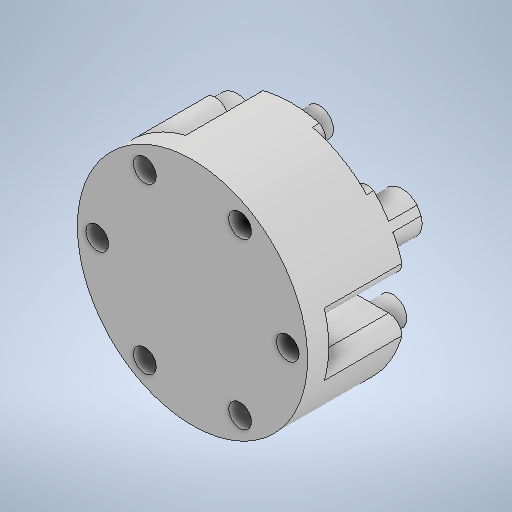
# Autodesk Inventor part: J1_J2_FLANGE
Saved by Autodesk Inventor 2025.4 (Build 294407000, 407)
## iProperties
Created: 2026-07-24
Part Number: J1_J2_FLANGE
Material: 常规
Document SubType Name: Modeling
Designer: Admin
Density: 1 g/cm^3
Appearance: 默认
Author: Admin
Autodesk Inventor part; units mm, degrees
ref_plane "YZ Plane" through (0, 0, 0) normal (1, 0, 0) x (0, 1, 0)
ref_plane "XZ Plane" through (0, 0, 0) normal (0, 1, 0) x (-1, 0, 0)
ref_plane "XY Plane" through (0, 0, 0) normal (0, 0, 1) x (1, 0, 0)
sketch "草图7" plane through (0, 0, 0) normal (0, 0, 1) x (1, 0, 0)
  line L0 (13.784, 2.5) -> (13.5, 2.5)
  line L1 (9.0571, 10.6873) -> (8.9151, 10.4413)
  arc A0 (12.2773, 11.0235) -> (9.0571, 10.6873) centre (10.7891, 9.6873) ccw
  arc A1 (15.6853, 5.1207) -> (12.2773, 11.0235) centre (0, 0) ccw
  arc A2 (13.784, 2.5) -> (15.6853, 5.1207) centre (13.784, 4.5) ccw
  circle A3 centre (0, 0) radius 17.5
  arc A4 (8.7635, -2.0496) -> (3.5969, 8.25) centre (0, 0) ccw
  line L2 (8.9151, 10.4413) -> (6.488, 6.2375)
  line L3 (6.488, 6.2375) -> (8.6458, 2.5)
  line L4 (8.6458, 2.5) -> (13.5, 2.5)
  line L5 (4.727, 13.1873) -> (4.5849, 12.9413)
  arc A5 (3.408, 16.1442) -> (-3.408, 16.1442) centre (0, 0) ccw
  arc A6 (4.727, 13.1873) -> (3.408, 16.1442) centre (2.9949, 14.1873) ccw
  line L6 (2.1578, 8.7375) -> (4.5849, 12.9413)
  line L7 (-4.727, 13.1873) -> (-4.5849, 12.9413)
  arc A7 (-3.408, 16.1442) -> (-4.727, 13.1873) centre (-2.9949, 14.1873) ccw
  line L8 (-4.5849, 12.9413) -> (-2.1578, 8.7375)
  line L9 (-2.1578, 8.7375) -> (2.1578, 8.7375)
  line L10 (-9.0571, 10.6873) -> (-8.9151, 10.4413)
  arc A8 (-12.2773, 11.0235) -> (-15.6853, 5.1207) centre (0, 0) ccw
  arc A9 (-9.0571, 10.6873) -> (-12.2773, 11.0235) centre (-10.7891, 9.6873) ccw
  line L11 (-6.488, 6.2375) -> (-8.9151, 10.4413)
  line L12 (-13.784, 2.5) -> (-13.5, 2.5)
  arc A10 (-15.6853, 5.1207) -> (-13.784, 2.5) centre (-13.784, 4.5) ccw
  line L13 (-13.5, 2.5) -> (-8.6458, 2.5)
  line L14 (-8.6458, 2.5) -> (-6.488, 6.2375)
  line L15 (-13.784, -2.5) -> (-13.5, -2.5)
  arc A11 (-15.6853, -5.1207) -> (-12.2773, -11.0235) centre (0, 0) ccw
  arc A12 (-13.784, -2.5) -> (-15.6853, -5.1207) centre (-13.784, -4.5) ccw
  line L16 (-8.6458, -2.5) -> (-13.5, -2.5)
  line L17 (-9.0571, -10.6873) -> (-8.9151, -10.4413)
  arc A13 (-12.2773, -11.0235) -> (-9.0571, -10.6873) centre (-10.7891, -9.6873) ccw
  line L18 (-8.9151, -10.4413) -> (-6.488, -6.2375)
  line L19 (-6.488, -6.2375) -> (-8.6458, -2.5)
  line L20 (-4.727, -13.1873) -> (-4.5849, -12.9413)
  arc A14 (-3.408, -16.1442) -> (3.408, -16.1442) centre (0, 0) ccw
  arc A15 (-4.727, -13.1873) -> (-3.408, -16.1442) centre (-2.9949, -14.1873) ccw
  line L21 (-2.1578, -8.7375) -> (-4.5849, -12.9413)
  line L22 (4.727, -13.1873) -> (4.5849, -12.9413)
  arc A16 (3.408, -16.1442) -> (4.727, -13.1873) centre (2.9949, -14.1873) ccw
  line L23 (4.5849, -12.9413) -> (2.1578, -8.7375)
  line L24 (2.1578, -8.7375) -> (-2.1578, -8.7375)
  line L25 (9.0571, -10.6873) -> (8.9151, -10.4413)
  arc A17 (12.2773, -11.0235) -> (15.6853, -5.1207) centre (0, 0) ccw
  arc A18 (9.0571, -10.6873) -> (12.2773, -11.0235) centre (10.7891, -9.6873) ccw
  line L26 (6.488, -6.2375) -> (8.9151, -10.4413)
  line L27 (13.784, -2.5) -> (13.5, -2.5)
  arc A19 (15.6853, -5.1207) -> (13.784, -2.5) centre (13.784, -4.5) ccw
  line L28 (13.5, -2.5) -> (8.6458, -2.5)
  line L29 (8.6458, -2.5) -> (6.488, -6.2375)
  point P0 (0, 0)
  dimension "d25" = 9
  dimension "d26" = 35
  dimension "d27" = 2
  dimension "d28" = 2
  dimension "d29" = 16.5
  dimension "d32" = 360
  constraints: 60 end point, 39 point on circle, 20 centre point, 4 coincident, 2 collinear, 1 equal length, 113 other
  measures "d25" radius of A4
  measures "d26" diameter of A3
  measures "d27" radius of A0
  measures "d28" radius of A2
  measures "d29" radius of A1
extrude "拉伸7" add sketch "草图7" against normal blind 1 contours L0 L4 A4 L2 L1 A0 A1 A2 | L3 A4 | L5 L6 L9 L8 L7 A7 A5 A6 | L10 L11 L14 L13 L12 A10 A8 A9 | L15 L16 L19 L18 L17 A13 A11 A12 | L20 L21 L24 L23 L22 A16 A14 A15 | L25 L26 L29 L28 L27 A19 A17 A18
sketch "草图8" plane through (0, 0, 0) normal (0, 0, 1) x (1, 0, 0)
  point P0 (0, 0)
sketch "草图9" plane through (0, 0, 0) normal (0, 0, 1) x (1, 0, 0)
  line L0 (9.0571, 10.6873) -> (6.488, 6.2375) projected
  line L1 (6.488, 6.2375) -> (8.6458, 2.5) projected
  line L2 (8.6458, 2.5) -> (13.784, 2.5) projected
  arc A0 (13.784, 2.5) -> (15.6853, 5.1207) centre (13.784, 4.5) ccw projected
  arc A1 (15.6853, 5.1207) -> (12.2773, 11.0235) centre (0, 0) ccw projected
  arc A2 (12.2773, 11.0235) -> (9.0571, 10.6873) centre (10.7891, 9.6873) ccw projected
  arc A3 (-3.408, 16.1442) -> (-4.727, 13.1873) centre (-2.9949, 14.1873) ccw projected
  line L3 (-4.727, 13.1873) -> (-2.1578, 8.7375) projected
  line L4 (-2.1578, 8.7375) -> (2.1578, 8.7375) projected
  line L5 (2.1578, 8.7375) -> (4.727, 13.1873) projected
  arc A4 (4.727, 13.1873) -> (3.408, 16.1442) centre (2.9949, 14.1873) ccw projected
  arc A5 (3.408, 16.1442) -> (-3.408, 16.1442) centre (0, 0) ccw projected
  arc A6 (15.6853, -5.1207) -> (13.784, -2.5) centre (13.784, -4.5) ccw projected
  line L6 (13.784, -2.5) -> (8.6458, -2.5) projected
  line L7 (8.6458, -2.5) -> (6.488, -6.2375) projected
  line L8 (6.488, -6.2375) -> (9.0571, -10.6873) projected
  arc A7 (9.0571, -10.6873) -> (12.2773, -11.0235) centre (10.7891, -9.6873) ccw projected
  arc A8 (12.2773, -11.0235) -> (15.6853, -5.1207) centre (0, 0) ccw projected
  arc A9 (3.408, -16.1442) -> (4.727, -13.1873) centre (2.9949, -14.1873) ccw projected
  line L9 (4.727, -13.1873) -> (2.1578, -8.7375) projected
  line L10 (2.1578, -8.7375) -> (-2.1578, -8.7375) projected
  line L11 (-2.1578, -8.7375) -> (-4.727, -13.1873) projected
  arc A10 (-4.727, -13.1873) -> (-3.408, -16.1442) centre (-2.9949, -14.1873) ccw projected
  arc A11 (-3.408, -16.1442) -> (3.408, -16.1442) centre (0, 0) ccw projected
  arc A12 (-12.2773, -11.0235) -> (-9.0571, -10.6873) centre (-10.7891, -9.6873) ccw projected
  line L12 (-9.0571, -10.6873) -> (-6.488, -6.2375) projected
  line L13 (-6.488, -6.2375) -> (-8.6458, -2.5) projected
  line L14 (-8.6458, -2.5) -> (-13.784, -2.5) projected
  arc A13 (-13.784, -2.5) -> (-15.6853, -5.1207) centre (-13.784, -4.5) ccw projected
  arc A14 (-15.6853, -5.1207) -> (-12.2773, -11.0235) centre (0, 0) ccw projected
  arc A15 (-15.6853, 5.1207) -> (-13.784, 2.5) centre (-13.784, 4.5) ccw projected
  line L15 (-13.784, 2.5) -> (-8.6458, 2.5) projected
  line L16 (-8.6458, 2.5) -> (-6.488, 6.2375) projected
  line L17 (-6.488, 6.2375) -> (-9.0571, 10.6873) projected
  arc A16 (-9.0571, 10.6873) -> (-12.2773, 11.0235) centre (-10.7891, 9.6873) ccw projected
  arc A17 (-12.2773, 11.0235) -> (-15.6853, 5.1207) centre (0, 0) ccw projected
  line L18 (6.488, 6.2375) -> (2.1578, 8.7375)
  arc A18 (12.2773, -11.0235) -> (15.6853, -5.1207) centre (0, 0) ccw
  arc A19 (-3.408, -16.1442) -> (3.408, -16.1442) centre (0, 0) ccw
  arc A20 (-15.6853, -5.1207) -> (-12.2773, -11.0235) centre (0, 0) ccw
  arc A21 (15.6853, 5.1207) -> (-3.408, 16.1442) centre (0, 0) ccw
  arc A22 (-12.2773, 11.0235) -> (-15.6853, 5.1207) centre (0, 0) ccw
  arc A23 (-12.2773, 11.0235) -> (-12.2773, -11.0235) centre (0, 0) ccw
  line L19 (-8.6458, 2.5) -> (-8.6458, -2.5)
  arc A24 (-3.408, -16.1442) -> (15.6853, -5.1207) centre (0, 0) ccw
  line L20 (2.1578, -8.7375) -> (6.488, -6.2375)
  point P0 (0, 0)
  point P1 (-8.6458, -2.5)
  point P2 (-15.6853, 5.1207)
  point P3 (-15.6853, -5.1207)
  point P4 (12.2773, -11.0235)
  point P5 (12.2773, 11.0235)
  point P6 (3.408, 16.1442)
  dimension "d38" = 360
  constraints: 24 point on circle, 7 centre point, 6 end point, 1 coincident, 22 other
extrude "拉伸8" add sketch "草图9" along normal blind 10
sketch "草图10" plane through (0, 0, -1) normal (0, 0, -1) x (-1, 0, 0)
  circle A0 centre (11.6913, 6.75) radius 3 projected
  circle A1 centre (10.3923, -6) radius 2 projected
  circle A2 centre (0, -13.5) radius 3 projected
  circle A3 centre (0, 12) radius 2 projected
  circle A4 centre (-11.6913, 6.75) radius 3 projected
  circle A5 centre (-10.3923, -6) radius 2 projected
  circle A6 centre (11.6913, 6.75) radius 2.85
  circle A7 centre (10.3923, -6) radius 1.975
  circle A8 centre (-11.6913, 6.75) radius 2.85
  circle A9 centre (0, 12) radius 1.975
  circle A10 centre (0, -13.5) radius 2.85
  circle A11 centre (-10.3923, -6) radius 1.975
  point P0 (0, 0)
  dimension "d71" = 5.7
  dimension "d72" = 3.95
  dimension "d75" = 360
  constraints: 6 centre point, 2 coincident, 13 other
  measures "d71" diameter of A6
  measures "d72" diameter of A7
extrude "拉伸9" add sketch "草图10" along normal blind 4 contours A6 | A7 | A8 | A9 | A10 | A11
sketch "草图11" plane through (0, 0, 0) normal (0, 0, -1) x (-1, 0, 0)
  line L0 (-5.939, 8.2866) -> (-4.8425, 6.3875) projected
  arc A0 (-5.939, 8.2866) -> (-7.2617, 9.2443) centre (-7.671, 7.2866) ccw projected
  arc A1 (-8.9151, 10.4413) -> (-7.2617, 9.2443) centre (-6.75, 11.6913) ccw projected
  line L1 (-9.0571, 10.6873) -> (-8.9151, 10.4413) projected
  arc A2 (-9.0571, 10.6873) -> (-12.2773, 11.0235) centre (-10.7891, 9.6873) ccw projected
  arc A3 (3.408, 16.1442) -> (-3.408, 16.1442) centre (0, 0) ccw
  arc A4 (-3.408, 16.1442) -> (-4.727, 13.1873) centre (-2.9949, 14.1873) ccw projected
  line L2 (-4.5849, 12.9413) -> (-4.727, 13.1873) projected
  arc A5 (-4.3749, 10.9109) -> (-4.5849, 12.9413) centre (-6.75, 11.6913) ccw projected
  arc A6 (-4.3749, 10.9109) -> (-4.2069, 9.2866) centre (-2.4749, 10.2866) ccw projected
  line L3 (-3.1105, 7.3875) -> (-4.2069, 9.2866) projected
  line L4 (-6.488, 6.2375) -> (-9.0571, 10.6873) projected
  line L5 (-2.1578, 8.7375) -> (-6.488, 6.2375) projected
  line L6 (-4.727, 13.1873) -> (-2.1578, 8.7375) projected
  point P0 (-3.4569, 7.9875)
  point P1 (-5.1889, 6.9875)
  constraints: 2 point on circle, 1 centre point
extrude "拉伸10" add sketch "草图11" along normal up to surface (1 mm away)
sketch "草图12" plane through (0, 0, -1) normal (0, 0, -1) x (-1, 0, 0)
  line L0 (-2.1578, 8.7375) -> (-6.488, 6.2375) projected
  circle A0 centre (0, 0) radius 9
  line L1 (-8.9151, 10.4413) -> (-9.0571, 10.6873) projected
  arc A1 (-9.0571, 10.6873) -> (-12.2773, 11.0235) centre (-10.7891, 9.6873) ccw projected
  arc A2 (-12.2773, 11.0235) -> (-15.6853, 5.1207) centre (0, 0) ccw projected
  arc A3 (-15.6853, 5.1207) -> (-13.784, 2.5) centre (-13.784, 4.5) ccw projected
  line L2 (-13.784, 2.5) -> (-8.6458, 2.5) projected
  line L3 (-8.6458, 2.5) -> (-6.488, 6.2375) projected
  line L4 (-6.488, 6.2375) -> (-5.1889, 6.9875) projected
  line L5 (-5.1889, 6.9875) -> (-5.939, 8.2866) projected
  arc A4 (-5.939, 8.2866) -> (-7.2617, 9.2443) centre (-7.671, 7.2866) ccw projected
  arc A5 (-8.9151, 10.4413) -> (-7.2617, 9.2443) centre (-6.75, 11.6913) ccw projected
  arc A6 (-4.3749, 10.9109) -> (-4.5849, 12.9413) centre (-6.75, 11.6913) ccw projected
  line L6 (-4.5849, 12.9413) -> (-4.727, 13.1873) projected
  arc A7 (-3.408, 16.1442) -> (-4.727, 13.1873) centre (-2.9949, 14.1873) ccw projected
  arc A8 (-3.408, 16.1442) -> (-12.2773, 11.0235) centre (0, 0) ccw projected
  arc A9 (-9.0571, 10.6873) -> (-12.2773, 11.0235) centre (-10.7891, 9.6873) ccw projected
  line L7 (-9.0571, 10.6873) -> (-8.9151, 10.4413) projected
  arc A10 (-8.9151, 10.4413) -> (-7.2617, 9.2443) centre (-6.75, 11.6913) ccw projected
  arc A11 (-5.939, 8.2866) -> (-7.2617, 9.2443) centre (-7.671, 7.2866) ccw projected
  line L8 (-5.939, 8.2866) -> (-5.1889, 6.9875) projected
  line L9 (-3.4569, 7.9875) -> (-5.1889, 6.9875) projected
  line L10 (-3.4569, 7.9875) -> (-4.2069, 9.2866) projected
  arc A12 (-4.3749, 10.9109) -> (-4.2069, 9.2866) centre (-2.4749, 10.2866) ccw projected
  arc A13 (4.727, 13.1873) -> (3.408, 16.1442) centre (2.9949, 14.1873) ccw projected
  arc A14 (3.408, 16.1442) -> (-3.408, 16.1442) centre (0, 0) ccw projected
  arc A15 (-3.408, 16.1442) -> (-4.727, 13.1873) centre (-2.9949, 14.1873) ccw projected
  line L11 (-4.727, 13.1873) -> (-4.5849, 12.9413) projected
  arc A16 (-4.3749, 10.9109) -> (-4.5849, 12.9413) centre (-6.75, 11.6913) ccw projected
  arc A17 (-4.3749, 10.9109) -> (-4.2069, 9.2866) centre (-2.4749, 10.2866) ccw projected
  line L12 (-4.2069, 9.2866) -> (-3.4569, 7.9875) projected
  line L13 (-3.4569, 7.9875) -> (-2.1578, 8.7375) projected
  line L14 (-2.1578, 8.7375) -> (2.1578, 8.7375) projected
  line L15 (2.1578, 8.7375) -> (4.727, 13.1873) projected
  point P0 (-3.6061, 8.246)
  point P1 (-5.3382, 7.246)
  constraints: 1 coincident, 3 other
extrude "拉伸11" cut sketch "草图12" against normal through all contours L0 L10 A0 | A0 L14 | L0 L5 A0 L10 | L0 A0 L5 | L3 A0
pattern_circular "环形阵列1" count 3 over 360 about axis through (0, 0, -10) along (0, 0, 1) of "拉伸11", "拉伸10"
sketch "草图13" plane through (0, 0, 10) normal (0, 0, 1) x (1, 0, 0)
  circle A0 centre (0, 0) radius 16.5
  constraints: 1 centre point, 1 coincident
extrude "拉伸12" add sketch "草图13" along normal blind 3
sketch "草图14" plane through (0, 0, 13) normal (0, 0, 1) x (1, 0, 0)
  circle A0 centre (6.75, -11.6913) radius 1.25 projected
  point P0 (0, 0)
  point P1 (13.5, 0)
  point P2 (6.75, 11.6913)
  point P3 (-6.75, 11.6913)
  point P4 (-13.5, 0)
  point P5 (-6.75, -11.6913)
  dimension "d55" = 360
  constraints: 1 coincident, 7 other
hole "孔1" at (-6.75, -11.6913, 13) at (-13.5, 0, 13) at (-6.75, 11.6913, 13) at (6.75, 11.6913, 13) at (13.5, 0, 13) at (6.75, -11.6913, 13) direction (0, 0, -1) diameter 3.2 end through all
sketch "草图16" plane through (0, 0, -1) normal (0, 0, -1) x (-1, 0, 0)
  arc A0 (-3.6061, 8.246) -> (-5.3382, 7.246) centre (0, 0) ccw projected
  line L0 (-3.6061, 8.246) -> (-4.2069, 9.2866) projected
  arc A1 (-4.3749, 10.9109) -> (-4.2069, 9.2866) centre (-2.4749, 10.2866) ccw projected
  arc A2 (-4.3749, 10.9109) -> (-4.5849, 12.9413) centre (-6.75, 11.6913) ccw projected
  line L1 (-4.5849, 12.9413) -> (-4.727, 13.1873) projected
  arc A3 (-3.408, 16.1442) -> (-4.727, 13.1873) centre (-2.9949, 14.1873) ccw projected
  arc A4 (-3.408, 16.1442) -> (-12.2773, 11.0235) centre (0, 0) ccw projected
  arc A5 (-9.0571, 10.6873) -> (-12.2773, 11.0235) centre (-10.7891, 9.6873) ccw projected
  line L2 (-9.0571, 10.6873) -> (-8.9151, 10.4413) projected
  arc A6 (-8.9151, 10.4413) -> (-7.2617, 9.2443) centre (-6.75, 11.6913) ccw projected
  arc A7 (-5.939, 8.2866) -> (-7.2617, 9.2443) centre (-7.671, 7.2866) ccw projected
  line L3 (-5.939, 8.2866) -> (-5.3382, 7.246) projected
  line L4 (-2.4749, 10.2866) -> (-4.2069, 9.2866)
  line L5 (-4.3749, 10.9109) -> (-2.4749, 10.2866)
  arc A8 (-3.408, 16.1442) -> (-4.727, 13.1873) centre (-2.9949, 14.1873) ccw projected
  line L6 (-2.9949, 14.1873) -> (-3.408, 16.1442)
  line L7 (-4.727, 13.1873) -> (-2.9949, 14.1873)
  line L8 (-4.5849, 12.9413) -> (-6.75, 11.6913)
  line L9 (-6.75, 11.6913) -> (-4.3749, 10.9109)
  line L10 (-5.939, 8.2866) -> (-7.671, 7.2866)
  line L11 (-7.671, 7.2866) -> (-7.2617, 9.2443)
  line L12 (-8.9151, 10.4413) -> (-6.75, 11.6913)
  line L13 (-7.2617, 9.2443) -> (-6.75, 11.6913)
  line L14 (-9.0571, 10.6873) -> (-10.7891, 9.6873)
  line L15 (-10.7891, 9.6873) -> (-12.2773, 11.0235)
  arc A9 (-12.2773, 11.0235) -> (-15.6853, 5.1207) centre (0, 0) ccw projected
  arc A10 (-3.3873, 16.0464) -> (-4.6404, 13.2373) centre (-2.9949, 14.1873) ccw
  arc A11 (-4.2799, 10.8797) -> (-4.1203, 9.3366) centre (-2.4749, 10.2866) ccw
  arc A12 (-4.2799, 10.8797) -> (-4.4983, 12.9913) centre (-6.75, 11.6913) ccw
  line L16 (-4.6404, 13.2373) -> (-4.4983, 12.9913)
  line L17 (-4.727, 13.1873) -> (-4.5849, 12.9413) projected
  arc A13 (-6.0256, 8.2366) -> (-7.2821, 9.1464) centre (-7.671, 7.2866) ccw
  arc A14 (-9.0017, 10.3913) -> (-7.2821, 9.1464) centre (-6.75, 11.6913) ccw
  arc A15 (-9.1437, 10.6373) -> (-12.2029, 10.9567) centre (-10.7891, 9.6873) ccw
  line L18 (-9.1437, 10.6373) -> (-9.0017, 10.3913)
  line L19 (-8.9151, 10.4413) -> (-9.0571, 10.6873) projected
  line L20 (-4.1203, 9.3366) -> (-3.5136, 8.2858)
  line L21 (-6.0256, 8.2366) -> (-5.4189, 7.1858)
  arc A16 (2.1578, 8.7375) -> (-3.6061, 8.246) centre (0, 0) ccw projected
  arc A17 (-5.3382, 7.246) -> (-8.6458, 2.5) centre (0, 0) ccw projected
  dimension "d77" = 0.1
  dimension "d78" = 0.1
  constraints: 32 end point, 16 point on circle, 10 point on line, 6 centre point, 6 coincident, 3 parallel, 2 collinear, 2 perpendicular, 2 tangent
  measures "d77" distance between parallel lines of L2 L18
  measures "d78" distance between parallel lines of L1 L16
extrude "拉伸14" cut sketch "草图16" against normal up to surface (1 mm away) contours L0 L4 L20 A16 | A17 L21 L10 L3 | A1 L5 A11 L4 | L10 A13 L11 A7 | A2 L1 L7 L16 A12 L5 | L11 A14 L18 L14 L2 A6 | A3 L6 A10 L7 | L14 A15 L15 A5
sketch "草图17" plane through (0, 0, -1) normal (0, 0, -1) x (-1, 0, 0)
  line L0 (-12.2029, 10.9567) -> (-12.2773, 11.0235) projected
  arc A0 (-12.2773, 11.0235) -> (-15.6853, 5.1207) centre (0, 0) ccw projected
  arc A1 (-15.6853, 5.1207) -> (-13.784, 2.5) centre (-13.784, 4.5) ccw projected
  line L1 (-13.784, 2.5) -> (-8.6458, 2.5) projected
  arc A2 (-5.4189, 7.1858) -> (-8.6458, 2.5) centre (0, 0) ccw projected
  line L2 (-5.4189, 7.1858) -> (-6.0256, 8.2366) projected
  arc A3 (-6.0256, 8.2366) -> (-7.2821, 9.1464) centre (-7.671, 7.2866) ccw projected
  arc A4 (-9.0017, 10.3913) -> (-7.2821, 9.1464) centre (-6.75, 11.6913) ccw projected
  line L3 (-9.0017, 10.3913) -> (-9.1437, 10.6373) projected
  arc A5 (-9.1437, 10.6373) -> (-12.2029, 10.9567) centre (-10.7891, 9.6873) ccw projected
  circle A6 centre (-11.6913, 6.75) radius 2.85 projected
  line L4 (-13.784, 4.5) -> (-13.784, 2.5)
  line L5 (-8.6163, 2.6) -> (-13.784, 2.6)
  line L6 (-13.784, 2.5) -> (-8.6458, 2.5) projected
  arc A7 (-15.5902, 5.0897) -> (-13.784, 2.6) centre (-13.784, 4.5) ccw
  arc A8 (-15.6853, 5.1207) -> (-15.6853, -5.1207) centre (0, 0) ccw projected
  line L7 (-15.6853, 5.1207) -> (-13.784, 4.5)
  circle A9 centre (-10.3923, -6) radius 1.975 projected
  arc A10 (-8.6458, -2.5) -> (-5.3382, -7.246) centre (0, 0) ccw projected
  line L8 (-8.6458, -2.5) -> (-13.784, -2.5) projected
  arc A11 (-13.784, -2.5) -> (-15.6853, -5.1207) centre (-13.784, -4.5) ccw projected
  arc A12 (-15.6853, -5.1207) -> (-12.2773, -11.0235) centre (0, 0) ccw projected
  arc A13 (-12.2773, -11.0235) -> (-9.0571, -10.6873) centre (-10.7891, -9.6873) ccw projected
  line L9 (-9.0571, -10.6873) -> (-8.9151, -10.4413) projected
  arc A14 (-7.2617, -9.2443) -> (-8.9151, -10.4413) centre (-6.75, -11.6913) ccw projected
  arc A15 (-7.2617, -9.2443) -> (-5.939, -8.2866) centre (-7.671, -7.2866) ccw projected
  line L10 (-5.939, -8.2866) -> (-5.3382, -7.246) projected
  arc A16 (-13.784, -2.5) -> (-15.6853, -5.1207) centre (-13.784, -4.5) ccw projected
  line L11 (-13.784, -4.5) -> (-13.784, -2.5)
  line L12 (-13.784, -4.5) -> (-15.6853, -5.1207)
  line L13 (-13.784, -2.6) -> (-8.6163, -2.6)
  line L14 (-8.6458, -2.5) -> (-13.784, -2.5) projected
  arc A17 (-13.784, -2.6) -> (-15.5902, -5.0897) centre (-13.784, -4.5) ccw
  dimension "d81" = 0.1
  dimension "d89" = 0.1
  constraints: 12 end point, 7 point on circle, 4 point on line, 2 centre point, 2 coincident, 2 parallel, 1 horizontal, 1 vertical
  measures "d81" distance between parallel lines of L1 L5
  measures "d89" distance between parallel lines of L13 L8
extrude "拉伸15" cut sketch "草图17" against normal up to surface (11 mm away) contours L7 A7 L4 A1 | L4 L5 A2 L1 | A10 L13 L11 L8 | L11 A17 L12 A11
sketch "草图18" plane through (0, 0, 13) normal (0, 0, 1) x (1, 0, 0)
  arc A0 (3.5136, 8.2858) -> (-2.1578, 8.7375) centre (0, 0) ccw projected
  circle A1 centre (0, 0) radius 16.3
  circle A2 centre (0, 0) radius 16.5 projected
  constraints: 1 centre point, 1 coincident
extrude "拉伸16" cut sketch "草图18" against normal through all
pattern_circular "环形阵列2" count 3 over 360 about axis through (0, 0, -10) along (0, 0, 1) of "拉伸14", "拉伸15"
sketch "草图19" plane through (0, 0, 10) normal (0, 0, -1) x (-1, 0, 0)
  circle A0 centre (0, 0) radius 9.25
  dimension "d90" = 18.5
  constraints: 1 centre point, 1 coincident
  measures "d90" diameter of A0
extrude "拉伸17" cut sketch "草图19" along normal blind 22.75
